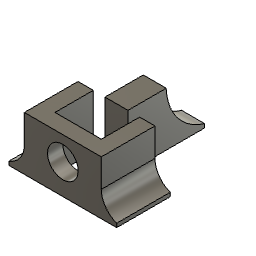
cygnus_4x6 (Autodesk Fusion 360 archive; units mm, degrees)
design "reset switch holder"
Autodesk Fusion 360 part; units mm, degrees
sketch "Sketch1" plane through (0, 0, 0) normal (0, 0, 1) x (1, 0, 0)
  line L0 (3.025, -3.025) -> (-3.025, -3.025)
  line L1 (-3.025, -3.025) -> (-3.025, 3.025)
  line L2 (-3.025, 3.025) -> (3.025, 3.025)
  line L3 (3.025, 3.025) -> (3.025, -3.025)
  line L4 (3.025, -3.025) -> (-3.025, 3.025) construction
  line L5 (-3.025, -3.025) -> (3.025, 3.025) construction
  circle A0 centre (0, 0) radius 1.7
  line L6 (-2.65, 3.025) -> (-1.9, 3.025)
  line L7 (-1.9, 3.025) -> (-1.9, 3.325)
  line L8 (-1.9, 3.325) -> (-2.65, 3.325)
  line L9 (-2.65, 3.325) -> (-2.65, 3.025)
  line L10 (0, 2.5) -> (0, 20)
  line L11 (2.65, 3.025) -> (1.9, 3.025)
  line L12 (1.9, 3.025) -> (1.9, 3.325)
  line L13 (2.65, 3.325) -> (2.65, 3.025)
  line L14 (1.9, 3.325) -> (2.65, 3.325)
  line L15 (20, 0) -> (2.5, 0)
  line L16 (-2.65, -3.025) -> (-1.9, -3.025)
  line L17 (-1.9, -3.025) -> (-1.9, -3.325)
  line L18 (-1.9, -3.325) -> (-2.65, -3.325)
  line L19 (-2.65, -3.325) -> (-2.65, -3.025)
  line L20 (2.65, -3.025) -> (1.9, -3.025)
  line L21 (1.9, -3.025) -> (1.9, -3.325)
  line L22 (2.65, -3.325) -> (2.65, -3.025)
  line L23 (1.9, -3.325) -> (2.65, -3.325)
  circle A1 centre (0, 0) radius 2
  circle A2 centre (0, 0) radius 1
  dimension "d1" = 6.05
  dimension "d2" = 6.05
  dimension "d3" = 3.4
  dimension "d4" = 0.75
  dimension "d5" = 0.3
  dimension "d6" = 0.375
  dimension "d25" = 4
  dimension "d28" = 2
  constraint horizontal L0
  constraint perpendicular L0 L1
  constraint parallel L0 L2
  constraint parallel L1 L3
  constraint coincident L4 A0.centre
  constraint coincident L5 A0.centre
  constraint coincident A0.centre A1.centre
  constraint horizontal L6
  constraint vertical L7
  constraint horizontal L8
  constraint vertical L9
  constraint coincident L2 L6.start
  constraint symmetric L6.start L10 L11.start
  constraint symmetric L6.end L10 L11.end
  constraint symmetric L7.end L10 L12.end
  constraint symmetric L8.end L10 L13.start
  constraint symmetric L6.start L15 L16.start
  constraint symmetric L6.end L15 L16.end
  constraint symmetric L7.end L15 L17.end
  constraint symmetric L8.end L15 L18.end
  constraint symmetric L11.start L15 L20.start
  constraint symmetric L11.end L15 L20.end
  constraint symmetric L12.end L15 L21.end
  constraint symmetric L13.start L15 L22.start
  measures "d1" distance of L1.end L2.end
  measures "d2" distance of L0.end L1.end
  measures "d3" diameter of A0
  measures "d4" distance of L6.start L6.end
  measures "d5" distance of L6.start L8.end
  measures "d6" distance of L1 L9
  measures "d25" diameter of A1
  measures "d28" diameter of A2
extrude "Extrude1" add sketch "Sketch1" against normal blind 3.7 contours L0 L1 L2 L3 L6 L11 L16 L20 | A0 | A1 | A2 makes body 1
extrude "Extrude2" add sketch "Sketch1" along normal blind 0.5 contours A0 | A2 bodies 1
extrude "Extrude3" add sketch "Sketch1" against normal blind 4.8 from surface at -2.7 contours L0 L20 L21 L22 L23 | L0 L16 L17 L18 L19 | L2 L11 L12 L13 L14 | L2 L6 L7 L8 L9 bodies 1
sketch "Sketch2" plane through (0, 0, 0) normal (0, 1, 0) x (1, 0, 0)
  line L0 (-3.025, 0) -> (3.025, 0)
  line L1 (-3.025, 0) -> (-3.025, 5)
  line L2 (3.025, 0) -> (3.025, 5)
  line L3 (-5.025, -2) -> (-5.025, 5)
  line L4 (-5.025, -2) -> (5.025, -2)
  line L5 (5.025, -2) -> (5.025, 5)
  line L6 (-5.025, 5) -> (-3.025, 5)
  line L7 (3.025, 5) -> (5.025, 5)
  line L8 (1.5, 5) -> (-1.5, 5)
  line L9 (-1.5, 5) -> (-1.5, 10)
  line L10 (-1.5, 10) -> (1.5, 10)
  line L11 (1.5, 10) -> (1.5, 5)
  line L12 (1.5, 10) -> (-1.5, 10)
  line L13 (-1.5, 10) -> (-1.5, 15)
  line L14 (-1.5, 15) -> (1.5, 15)
  line L15 (1.5, 15) -> (1.5, 10)
  line L16 (-5.025, 5) -> (-7.025, 5)
  line L17 (-7.025, 5) -> (-7.025, -2)
  line L18 (-7.025, -2) -> (-5.025, -2)
  line L19 (5.025, 5) -> (7.025, 5)
  line L20 (7.025, 5) -> (7.025, -2)
  line L21 (7.025, -2) -> (5.025, -2)
  dimension "d14" = 5
  dimension "d15" = 5
  dimension "d16" = -2
  dimension "d17" = 3
  dimension "d18" = 5
  dimension "d19" = 5
  dimension "d20" = 6.05
  dimension "d21" = 1.525
  dimension "d29" = 5
  dimension "d30" = 3
  dimension "d31" = 2
  dimension "d32" = 2
  constraint perpendicular L0 L1
  constraint perpendicular L0 L2
  constraint perpendicular L1 L6
  constraint horizontal L8
  constraint vertical L9
  constraint horizontal L10
  constraint vertical L11
  constraint horizontal L12
  constraint vertical L13
  constraint horizontal L14
  constraint vertical L15
  constraint perpendicular L3 L16
  constraint perpendicular L4 L17
  constraint perpendicular L17 L18
  constraint perpendicular L5 L19
  constraint perpendicular L4 L20
  constraint perpendicular L5 L21
  measures "d14" distance of L0.start L1.end
  measures "d15" distance of L0.end L2.end
  measures "d17" distance of L8.start L8.end
  measures "d18" distance of L8.start L10.end
  measures "d19" distance of L0 L8
  measures "d20" distance of L0.start L0.end
  measures "d21" distance of L2 L11
  measures "d29" distance of L10.end L14.end
  measures "d30" distance of L13 L15
  measures "d31" distance of L3.end L16.end
  measures "d32" distance of L5.end L19.end
extrude "Extrude4" add sketch "Sketch2" along normal blind 6.5 from surface at -3.4 separate body contours L0 L1 L2 L3 L4 L5 L6 L7 | L8 L9 L10 L11 L12 makes body 2 at (-1.675, -1.2333, 2) makes body 3 at (-1.5, -1.2333, -6.6667)
extrude "Extrude5" cut sketch "Sketch1" along normal blind 3.3 contours A0 | A1 | A2 bodies 2
extrude "Extrude6" add sketch "Sketch2" against normal blind 0.5 from surface at -3.4 bodies 2 3
fillet "Fillet1" radius 7 1 edges at (0, -3.4, -10) on bodies 3
fillet "Fillet2" radius 3 2 edges at (5.025, -3.4, -1.5) (-5.025, -3.4, -1.5) on bodies 2
hidden bodies 1
equation "d21 = ( d20 - d17 ) / 2"
equation "d30 = d17"
